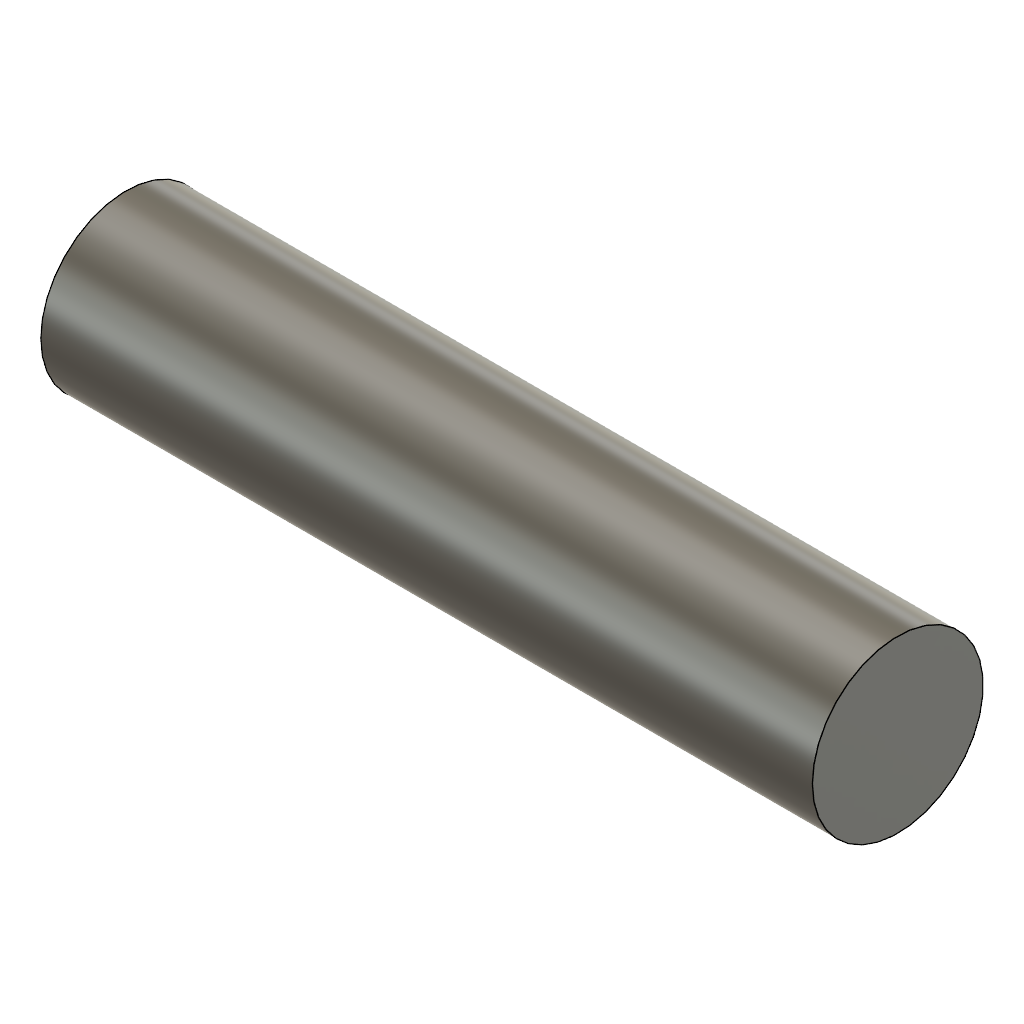
holdout_c_edit_first (Autodesk Fusion 360 design; units mm, degrees)
part number: 2026-11-27-17-36-51-262
Autodesk Fusion 360 part; units mm, degrees
sketch "CircularProfile" plane through (0, 0, 0) normal (1, 0, 0) x (0, 0, -1)
  circle A0 centre (-23, 17) radius 5.3
extrude "OffsetTwoSides" add sketch "CircularProfile" along normal blind 6.125 and the other way blind 41.75 from surface at -61
